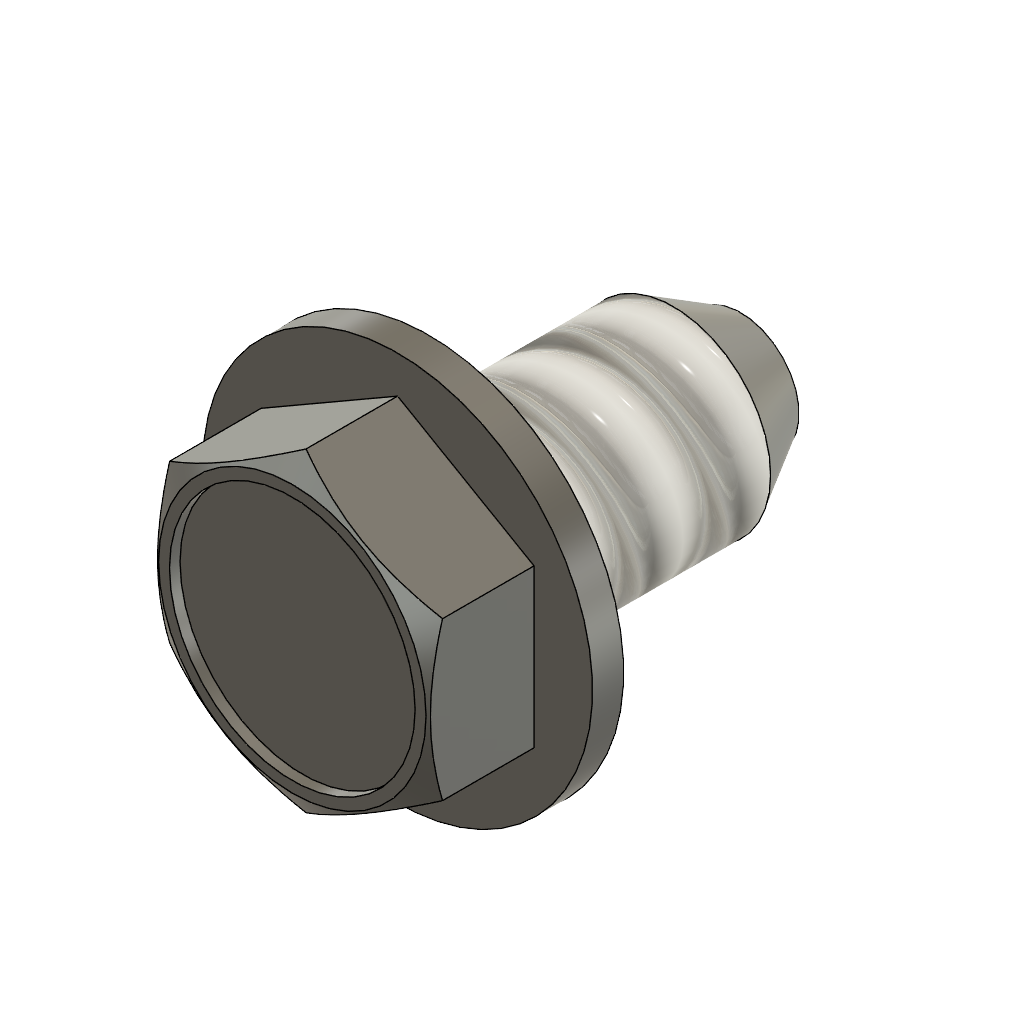
Diseño Avance 3 (Autodesk Fusion 360 archive; units mm, degrees)
design "Tornillo grueso en forma de rosca sin ranura de arandela hexagonal 30° 5x8 Acero al carbono Negro"
description: Tornillo grueso en forma de rosca sin ranura de arandela hexagonal 30° 5x8
Autodesk Fusion 360 part; units mm, degrees
sketch "Sketch1" plane through (0, 0, 0) normal (0, 1, 0) x (1, 0, 0)
  line L0 (-2.5, 0) -> (-2.5, 8)
  line L1 (-2.5, 8) -> (0, 8)
  line L2 (0, 8) -> (0, -3.5)
  line L3 (-2.5, 0) -> (-5, 0)
  line L4 (-5, 0) -> (-5, -3.5)
  line L5 (-5, -3.5) -> (0, -3.5)
  dimension "d9" = 5
  dimension "d66" = 10
  dimension "d68" = 8
  dimension "d73" = 3.5
  constraint perpendicular L0 L1
  constraint collinear origin L2.end L1.end
  constraint perpendicular L0 L3
  constraint coincident origin L3
  constraint vertical L0
  constraint vertical L2
  constraint perpendicular L3 L4
  constraint perpendicular L4 L5
  constraint coincident L2.end L5
  constraint coincident L2.end L5.end
  measures "d68" distance of origin L1.end
  measures "d73" distance of L3.end L4.end
revolve "Revolve1" add sketch "Sketch1" angle 360 about axis through (0, 0, -8) along (0, 0, 1)
ref_plane "WorkPlane2" through (0, 0, 3.5) normal (0, 0, 1) x (1, 0, 0)
sketch "Sketch6" plane through (0, 0, 3.5) normal (0, 0, 1) x (1, 0, 0)
  circle A0 centre (0, 0) radius 5
  line L0 (0, 0) -> (-3.5, 0) construction
  line L1 (0, 0) -> (-3.5, -2.0207)
  line L2 (0, 0) -> (2.5495, 0) construction
  line L3 (-3.5, 2.0207) -> (-3.5, -2.0207)
  line L4 (0, 0) -> (-3.5, 2.0207)
  line L5 (0, 0) -> (0, 4.0415)
  line L6 (-3.5, 2.0207) -> (0, 4.0415)
  line L7 (3.5, 2.0207) -> (0, 4.0415)
  line L8 (0, 0) -> (3.5, 2.0207)
  line L9 (0, -4.0415) -> (-3.5, -2.0207)
  line L10 (0, -4.0415) -> (3.5, -2.0207)
  line L11 (3.5, 2.0207) -> (3.5, -2.0207)
  dimension "d76" = 3.5
  dimension "d77" = 150
  constraint coincident A0.centre L0.start
  constraint horizontal L0
  constraint horizontal L2
  constraint perpendicular L0 L3
  constraint midpoint L0.end L3
  constraint coincident L1 L3.end
  constraint coincident L1.end L3
  constraint symmetric L0 A0.centre L1.start
  constraint symmetric L0 L1.end L3.start
  constraint symmetric A0.centre L4 L0.start
  constraint symmetric L1.end L4 L5.end
  constraint symmetric L3.start L4 L6.start
  constraint symmetric A0.centre L5 L0.start
  constraint symmetric L3.start L5 L7.start
  constraint symmetric L5 L3.start L7.start
  constraint symmetric L5 L6.end L7.end
  constraint symmetric L3.start L8 L9.start
  constraint symmetric L1.end L8 L3.end
  constraint symmetric L5.end L8 L10.end
  constraint symmetric L7.start L8 L11.start
  measures "d76" distance of A0.centre L0.end
  measures "d77" angle of L1 L2
extrude "Extrude2" cut sketch "Sketch6" against normal blind 2.7
sketch "Sketch8" plane through (0, 0, 3.5) normal (0, 0, 1) x (1, 0, 0)
  circle A0 centre (0, 0) radius 3.43
  circle A1 centre (0, 0) radius 6
  dimension "d80" = 6.86
  dimension "d81" = 12
  constraint coincident A0.centre A1.centre
  measures "d80" diameter of A0
  measures "d81" diameter of A1
extrude "Extrude3" cut sketch "Sketch8" against normal blind 3.5 draft -60
sketch "Sketch9" plane through (0, 0, 3.5) normal (0, 0, 1) x (1, 0, 0)
  circle A0 centre (0, 0) radius 3.15
  dimension "d84" = 6.3
  constraint coincident A0.centre origin
  measures "d84" diameter of A0
extrude "Extrude4" cut sketch "Sketch9" against normal blind 0.27
ref_plane "WorkPlane1" through (0, 0, 3.95) normal (0, 0, 1) x (1, 0, 0)
sketch "Sketch5" plane through (0, 0, 0) normal (0, 1, 0) x (1, 0, 0)
  line L0 (-2.5, 8) -> (0, 8)
  line L1 (-2.5, 0) -> (-2.5, 8)
  line L2 (-2.5, 6.2679) -> (-1.5, 8)
  dimension "d39" = 30
  dimension "d40" = 1
  constraint coincident L1 L2.start
  constraint coincident L0 L2.end
  measures "d39" angle of L1 L2
  measures "d40" distance of L0.start L2.end
thread "Thread1" "Metric Tapping Threads for Plastics 5.0 5x2.24 5x2.24 h14" major diameter 5 minor diameter 2.68 pitch 2.24 angle 30 resizes the face on face at (-2.4876, 0.2489, -2.6667)
revolve "Revolve2" cut sketch "Sketch5" angle 360 about axis through (0, 0, -8) along (0, 0, 1)
equation "d9 = NND"
equation "NLG = 8 mm"
equation "KOH = 3.5 mm"
equation "KOD = 10 mm"
equation "NND = 5 mm"
equation "d40 = NND * 0.2"
equation "d66 = KOD"
equation "d68 = NLG"
equation "d71 = KOH + KOF - KOH * 0.1"
equation "KOF = 0.8 mm"
equation "d73 = KOH"
equation "d74 = KOH"
equation "SW = 7 mm"
equation "d76 = SW / 2"
equation "d78 = -KOH + KOF"
equation "d80 = SW * 0.98"
equation "d81 = KOD * 1.2"
equation "d82 = -KOH"
equation "d84 = SW * 0.9"
equation "d85 = ( -KOH + KOF ) * 0.1"
